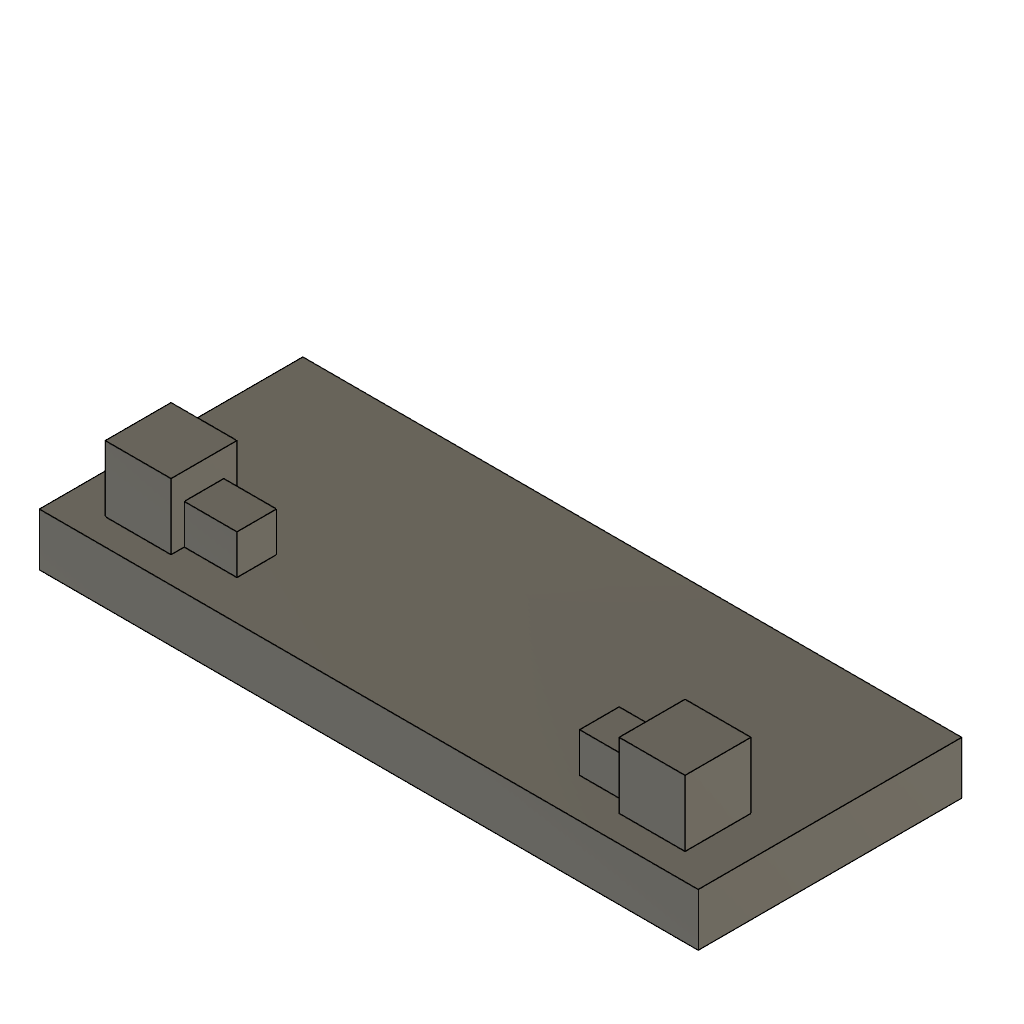
join_absorbs_new_body_mirror (Autodesk Fusion 360 design; units mm, degrees)
Autodesk Fusion 360 part; units mm, degrees
sketch "Sketch1" plane through (0, 0, 0) normal (0, 0, 1) x (1, 0, 0)
  line L0 (0, 0) -> (50, 0)
  line L1 (50, 0) -> (50, 20)
  line L2 (50, 20) -> (0, 20)
  line L3 (0, 20) -> (0, 0)
extrude "Extrude1" add sketch "Sketch1" along normal blind 4 makes body 1
ref_plane "WorkPlane1" through (0, 0, 4) normal (0, 0, 1) x (1, 0, 0)
sketch "Sketch2" plane through (0, 0, 4) normal (0, 0, 1) x (1, 0, 0)
  line L0 (3, 2) -> (8, 2)
  line L1 (8, 2) -> (8, 7)
  line L2 (8, 7) -> (3, 7)
  line L3 (3, 7) -> (3, 2)
extrude "Extrude2" add sketch "Sketch2" along normal blind 5 separate body makes body 2
ref_plane "WorkPlane2" through (0, 0, 4) normal (0, 0, 1) x (1, 0, 0)
sketch "Sketch3" plane through (0, 0, 4) normal (0, 0, 1) x (1, 0, 0)
  line L0 (6, 3) -> (12, 3)
  line L1 (12, 3) -> (12, 6)
  line L2 (12, 6) -> (6, 6)
  line L3 (6, 6) -> (6, 3)
extrude "Extrude3" add sketch "Sketch3" along normal blind 3 bodies 1 2
ref_plane "WorkPlane3" through (25, 0, 0) normal (1, 0, 0) x (0, 1, 0)
mirror "Mirror1" about plane through (25, 0, 0) normal (1, 0, 0) of "Extrude2", "Extrude3"
named bodies: "Plate", "Block"
